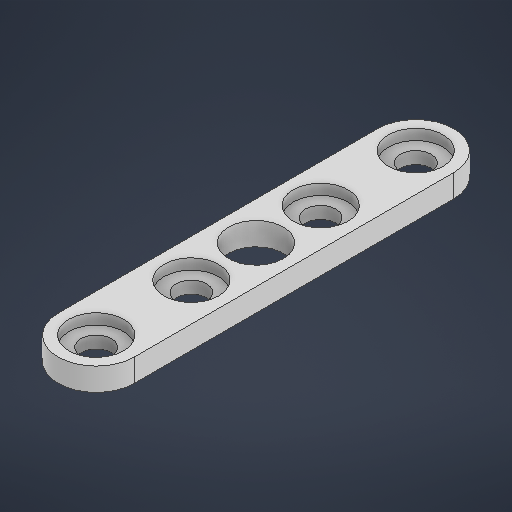
# Autodesk Inventor part: trzymanie_kola2
Saved by Autodesk Inventor 2026.1 (Build 301233020, 233B)
## iProperties
Created: 2026-07-11
Part Number: trzymanie_kola2
Material: Ogólny
Document SubType Name: Modeling
Designer: Nitro
Density: 1 g/cm^3
Appearance: Domyślna
Author: Nitro
Autodesk Inventor part; units mm, degrees
ref_plane "YZ Plane" through (0, 0, 0) normal (1, 0, 0) x (0, 1, 0)
ref_plane "XZ Plane" through (0, 0, 0) normal (0, 1, 0) x (-1, 0, 0)
ref_plane "XY Plane" through (0, 0, 0) normal (0, 0, 1) x (1, 0, 0)
sketch "Szkic1" plane through (0, 0, 0) normal (0, 1, 0) x (-1, 0, 0)
  line L0 (0, 0) -> (0, -42) construction
  line L1 (-5, 0) -> (-5, -42)
  line L2 (5, -42) -> (5, 0)
  arc A0 (5, 0) -> (-5, 0) centre (0, 0) ccw
  arc A1 (-5, -42) -> (5, -42) centre (0, -42) ccw
  point P0 (0, -21)
  dimension "d0" = 42
  dimension "d1" = 10
  constraints: 8 end point, 4 point on circle, 4 tangent, 2 centre point, 1 midpoint, 1 parallel, 1 vertical
  measures "d0" distance of L0.start L0.end
  measures "d1" diameter of A1
extrude "Wyciągnięcie proste1" add sketch "Szkic1" along normal blind 3.5
sketch "Szkic2" plane through (0, 3.5, 0) normal (0, 1, 0) x (1, 0, 0)
  circle A0 centre (0, 0) radius 1.5
  circle A1 centre (0, 42) radius 1.5
  dimension "d4" = 3
  dimension "d5" = 3
  dimension "d6" = 42
  constraints: 2 centre point, 1 coincident
  measures "d4" diameter of A0
  measures "d5" diameter of A1
  measures "d6" distance of point (0, 0) A1.centre
extrude "Wyciągnięcie proste2" cut sketch "Szkic2" against normal blind 3.5
sketch "Szkic3" plane through (0, 3.5, 0) normal (0, 1, 0) x (1, 0, 0)
  circle A0 centre (0, 42) radius 1.5 projected
  circle A1 centre (0, 0) radius 1.5 projected
  arc A2 (5, 42) -> (-5, 42) centre (0, 42) ccw projected
  line L0 (-5, 42) -> (-5, 0) projected
  arc A3 (-5, 0) -> (5, 0) centre (0, 0) ccw projected
  line L1 (5, 0) -> (5, 42) projected
  circle A4 centre (0, 0) radius 2.35
  circle A5 centre (0, 42) radius 2.35
  dimension "d9" = 4.7
  dimension "d10" = 4.7
  constraints: 2 centre point, 2 coincident
  measures "d9" diameter of A4
  measures "d10" diameter of A5
extrude "Wyciągnięcie proste3" cut sketch "Szkic3" against normal blind 0.4 contours A0 | A1 | A4 | A5
sketch "Szkic4" plane through (0, 3.5, 0) normal (0, 1, 0) x (1, 0, 0)
  circle A0 centre (0, 42) radius 2.35 projected
  circle A1 centre (0, 0) radius 2.35 projected
  arc A2 (5, 42) -> (-5, 42) centre (0, 42) ccw projected
  line L0 (-5, 42) -> (-5, 0) projected
  arc A3 (-5, 0) -> (5, 0) centre (0, 0) ccw projected
  line L1 (5, 0) -> (5, 42) projected
  point P0 (0, 12.5)
  point P1 (0, 29.5)
  dimension "d13" = 12.5
  dimension "d14" = 12.5
  measures "d13" distance of A0.centre point (0, 29.5)
  measures "d14" distance of point (0, 0) point (0, 12.5)
hole "Otwór1" at (0, 3.5, -12.5) at (0, 3.5, -29.5) direction (0, -1, 0) diameter 4 depth 10
sketch "Szkic5" plane through (0, 3.5, 0) normal (0, 1, 0) x (1, 0, 0)
  circle A0 centre (0, 29.5) radius 2 projected
  circle A1 centre (0, 12.5) radius 2 projected
  circle A2 centre (0, 42) radius 2.35 projected
  circle A3 centre (0, 0) radius 2.35 projected
  arc A4 (5, 42) -> (-5, 42) centre (0, 42) ccw projected
  line L0 (-5, 42) -> (-5, 0) projected
  arc A5 (-5, 0) -> (5, 0) centre (0, 0) ccw projected
  line L1 (5, 0) -> (5, 42) projected
  circle A6 centre (0, 12.5) radius 3.6
  circle A7 centre (0, 29.5) radius 3.6
  circle A8 centre (0, 21) radius 3.6
  dimension "d22" = 7.2
  dimension "d23" = 7.2
  dimension "d24" = 7.2
  constraints: 3 centre point, 2 coincident
  measures "d22" diameter of A6
  measures "d23" diameter of A7
  measures "d24" diameter of A8
extrude "Wyciągnięcie proste4" cut sketch "Szkic5" against normal blind 0.4 contours A6 | A7
sketch "Szkic6" plane through (0, 3.5, 0) normal (0, 1, 0) x (1, 0, 0)
  circle A0 centre (0, 29.5) radius 3.6 projected
  circle A1 centre (0, 12.5) radius 3.6 projected
  circle A2 centre (0, 42) radius 2.35 projected
  circle A3 centre (0, 0) radius 2.35 projected
  arc A4 (5, 42) -> (-5, 42) centre (0, 42) ccw projected
  line L0 (-5, 42) -> (-5, 0) projected
  arc A5 (-5, 0) -> (5, 0) centre (0, 0) ccw projected
  line L1 (5, 0) -> (5, 42) projected
  circle A6 centre (0, 21) radius 3.6
  dimension "d27" = 7.2
  constraints: 1 centre point, 1 coincident
  measures "d27" diameter of A6
extrude "Wyciągnięcie proste5" cut sketch "Szkic6" against normal blind 95 contours A6
sketch "Szkic7" plane through (0, 0, 0) normal (0, -1, 0) x (1, 0, 0)
  circle A0 centre (0, -21) radius 3.6 projected
  circle A1 centre (0, -29.5) radius 2 projected
  circle A2 centre (0, -12.5) radius 2 projected
  circle A3 centre (0, -42) radius 1.5 projected
  circle A4 centre (0, 0) radius 1.5 projected
  arc A5 (-5, -42) -> (5, -42) centre (0, -42) ccw projected
  line L0 (5, 0) -> (5, -42) projected
  arc A6 (5, 0) -> (-5, 0) centre (0, 0) ccw projected
  line L1 (-5, -42) -> (-5, 0) projected
extrude "Wyciągnięcie proste6" cut sketch "Szkic7" against normal blind 0.5
sketch "Szkic8" plane through (0, 3.1, -12.5) normal (0, 1, 0) x (1, 0, 0)
  circle A0 centre (0, -12.5) radius 1.5 projected
  circle A1 centre (0, -12.5) radius 2.35 projected
  circle A2 centre (0, 0) radius 3.6 projected
  circle A3 centre (0, 0) radius 2 projected
  circle A4 centre (0, 17) radius 3.6 projected
  circle A5 centre (0, 17) radius 2 projected
  circle A6 centre (0, 29.5) radius 1.5 projected
  circle A7 centre (0, 29.5) radius 2.35 projected
extrude "Wyciągnięcie proste7" cut sketch "Szkic8" against normal blind 1 contours A0 | A1 | A2 | A4 | A6 | A7
sketch "Szkic9" plane through (0, 3.5, 0) normal (0, 1, 0) x (1, 0, 0)
  circle A0 centre (0, 0) radius 2.35 projected
  circle A1 centre (0, 0) radius 2
  circle A2 centre (0, 42) radius 1.5 projected
  circle A3 centre (0, 42) radius 2
  dimension "d34" = 4
  dimension "d35" = 4
  constraints: 2 centre point, 2 coincident
  measures "d34" diameter of A1
  measures "d35" diameter of A3
extrude "Wyciągnięcie proste8" cut sketch "Szkic9" against normal blind 10 contours A1 | A2 | A3
sketch "Szkic10" plane through (0, 3.5, 0) normal (0, 1, 0) x (1, 0, 0)
  circle A0 centre (0, 0) radius 3.6
  circle A1 centre (0, 21) radius 3.6 projected
  circle A2 centre (0, 29.5) radius 3.6 projected
  circle A3 centre (0, 12.5) radius 3.6 projected
  circle A4 centre (0, 42) radius 2.35 projected
  circle A5 centre (0, 0) radius 2.35 projected
  arc A6 (5, 42) -> (-5, 42) centre (0, 42) ccw projected
  line L0 (-5, 42) -> (-5, 0) projected
  arc A7 (-5, 0) -> (5, 0) centre (0, 0) ccw projected
  line L1 (5, 0) -> (5, 42) projected
  circle A8 centre (0, 42) radius 3.6
  dimension "d38" = 7.2
  dimension "d39" = 7.2
  constraints: 2 centre point, 2 coincident
  measures "d38" diameter of A0
  measures "d39" diameter of A8
extrude "Wyciągnięcie proste9" cut sketch "Szkic10" against normal blind 1.4 contours A0 | A8
